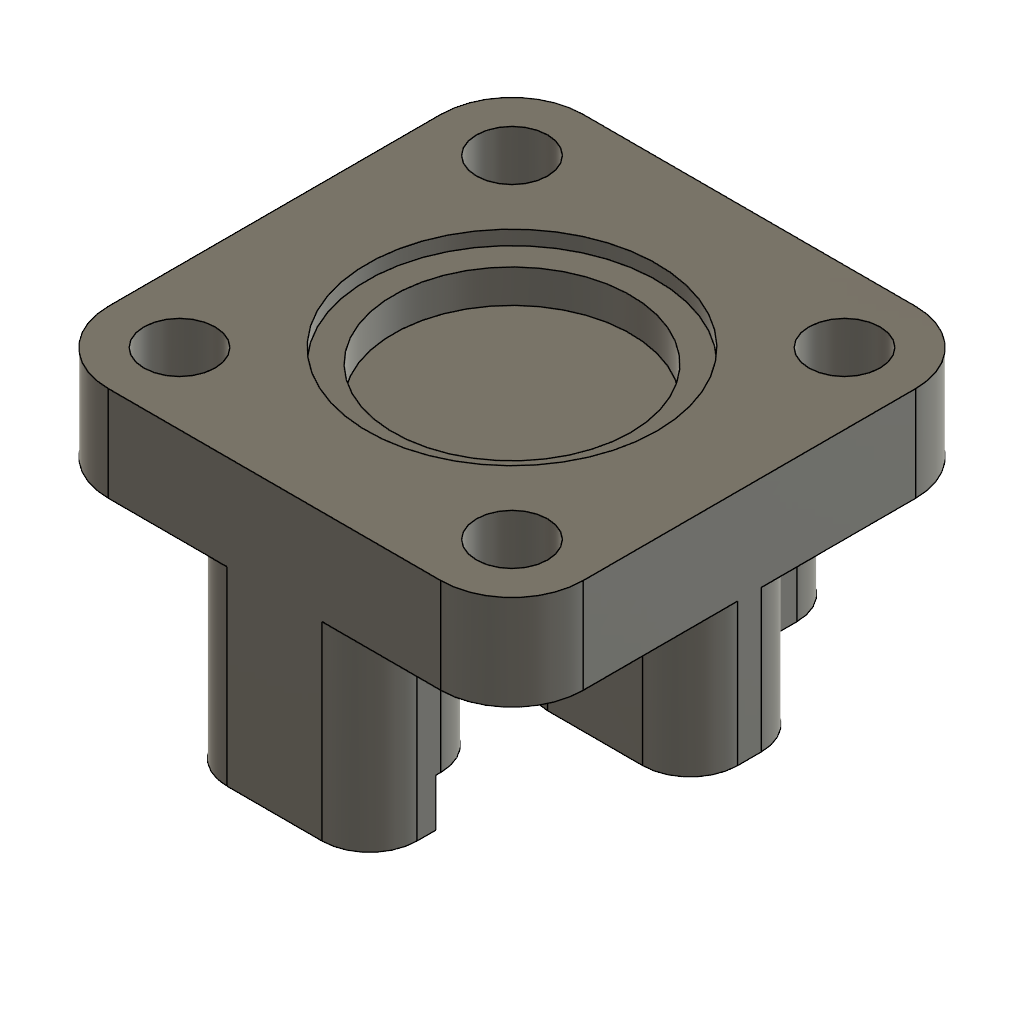
02-20_베어링커버 (Autodesk Fusion 360 design; units mm, degrees)
Autodesk Fusion 360 part; units mm, degrees
sketch "스케치1" plane through (0, 0, 0) normal (0, 1, 0) x (1, 0, 0)
  line L0 (-7, 10) -> (7, 10)
  line L1 (10, 7) -> (10, -7)
  line L2 (7, -10) -> (-7, -10)
  line L3 (-10, -7) -> (-10, 7)
  line L4 (0, 10) -> (0, -10) construction
  arc A0 (-7, 10) -> (-10, 7) centre (-7, 7) ccw
  arc A1 (10, 7) -> (7, 10) centre (7, 7) ccw
  arc A2 (7, -10) -> (10, -7) centre (7, -7) ccw
  arc A3 (-10, -7) -> (-7, -10) centre (-7, -7) ccw
  point P0 (-10, 10)
  point P1 (10, 10)
  point P2 (10, -10)
  dimension "d1" = 20
  dimension "d2" = 20
  dimension "d3" = 3
  constraint horizontal L0
  constraint vertical L1
  constraint horizontal L2
  constraint vertical L3
  constraint midpoint origin L4
  constraint coincident L0 L4.start
  constraint coincident P0 L3
  constraint coincident P0 L0
  constraint tangent L3 A0
  constraint tangent L0 A0
  constraint coincident P1 L0
  constraint coincident P1 L1
  constraint tangent L0 A1
  constraint tangent L1 A1
  constraint equal A0 A1
  constraint coincident L2 L4.end
  constraint coincident P2 L1
  constraint coincident P2 L2
  constraint tangent L1 A2
  constraint tangent L2 A2
  constraint equal A0 A2
  constraint tangent L2 A3
  constraint tangent L3 A3
  constraint equal A0 A3
  measures "d1" distance of P0 P1
  measures "d2" distance of P1 P2
  measures "d3" radius of A0
extrude "돌출1" add sketch "스케치1" along normal blind 4
sketch "스케치2" plane through (0, 4, 0) normal (0, 1, 0) x (-1, 0, 0)
  arc A0 (7, -10) -> (10, -7) centre (7, -7) ccw
  line L0 (10, -7) -> (10, 7)
  arc A1 (10, 7) -> (7, 10) centre (7, 7) ccw
  line L1 (7, 10) -> (-7, 10)
  arc A2 (-7, 10) -> (-10, 7) centre (-7, 7) ccw
  line L2 (-10, 7) -> (-10, -7)
  arc A3 (-10, -7) -> (-7, -10) centre (-7, -7) ccw
  line L3 (-7, -10) -> (7, -10)
  circle A4 centre (0, 0) radius 6.1
  circle A5 centre (0, 0) radius 5
  circle A6 centre (7, -7) radius 1.5
  circle A7 centre (-7, -7) radius 1.5
  circle A8 centre (-7, 7) radius 1.5
  circle A9 centre (7, 7) radius 1.5
  dimension "d6" = 12.2
  dimension "d7" = 10
  dimension "d12" = 3
  dimension "d13" = 3
  dimension "d14" = 3
  dimension "d15" = 3
  constraint coincident A4.centre A5.centre
  constraint concentric A4 A5
  constraint concentric A0 A6
  constraint concentric A3 A7
  constraint concentric A2 A8
  constraint concentric A1 A9
  measures "d6" diameter of A4
  measures "d7" diameter of A5
  measures "d12" diameter of A6
  measures "d13" diameter of A7
  measures "d14" diameter of A8
  measures "d15" diameter of A9
extrude "돌출2" cut sketch "스케치2" against normal blind 2 contours A5
extrude "돌출3" cut sketch "스케치2" against normal blind 0.6 contours A4
extrude "돌출4" cut sketch "스케치2" against normal blind 4 contours A6 | A7 | A8 | A9
sketch "스케치3" plane through (0, 0, 0) normal (0, -1, 0) x (1, 0, 0)
  circle A0 centre (7, 7) radius 1.5
  circle A1 centre (7, -7) radius 1.5
  circle A2 centre (-7, 7) radius 1.5
  circle A3 centre (-7, -7) radius 1.5
  arc A4 (-10, -7) -> (-7, -10) centre (-7, -7) ccw
  line L0 (-7, -10) -> (7, -10)
  arc A5 (7, -10) -> (10, -7) centre (7, -7) ccw
  line L1 (10, -7) -> (10, 7)
  arc A6 (10, 7) -> (7, 10) centre (7, 7) ccw
  line L2 (7, 10) -> (-7, 10)
  arc A7 (-7, 10) -> (-10, 7) centre (-7, 7) ccw
  line L3 (-10, 7) -> (-10, -7)
  line L4 (-2, 10) -> (2, 10)
  line L5 (4, 8) -> (4, 7)
  line L6 (2, 5) -> (-2, 5)
  line L7 (-4, 7) -> (-4, 8)
  line L8 (0, 10) -> (0, -10) construction
  line L9 (-10, 0) -> (10, 0) construction
  arc A8 (-2, 10) -> (-4, 8) centre (-2, 8) ccw
  arc A9 (-4, 7) -> (-2, 5) centre (-2, 7) ccw
  arc A10 (2, 5) -> (4, 7) centre (2, 7) ccw
  arc A11 (4, 8) -> (2, 10) centre (2, 8) ccw
  line L10 (4, -8) -> (4, -7)
  arc A12 (2, -10) -> (4, -8) centre (2, -8) ccw
  line L11 (-2, -10) -> (2, -10)
  arc A13 (-4, -8) -> (-2, -10) centre (-2, -8) ccw
  line L12 (-4, -7) -> (-4, -8)
  arc A14 (-2, -5) -> (-4, -7) centre (-2, -7) ccw
  line L13 (2, -5) -> (-2, -5)
  arc A15 (4, -7) -> (2, -5) centre (2, -7) ccw
  line L14 (-4, 7.2) -> (4, 7.2)
  line L15 (-4, -7.2) -> (4, -7.2)
  line L16 (4, 2.5) -> (8, 2.5)
  line L17 (10, 0.5) -> (10, -0.5)
  line L18 (8, -2.5) -> (4, -2.5)
  line L19 (2, -0.5) -> (2, 0.5)
  circle A16 centre (6, 0) radius 1.1
  arc A17 (4, 2.5) -> (2, 0.5) centre (4, 0.5) ccw
  arc A18 (10, 0.5) -> (8, 2.5) centre (8, 0.5) ccw
  arc A19 (8, -2.5) -> (10, -0.5) centre (8, -0.5) ccw
  arc A20 (2, -0.5) -> (4, -2.5) centre (4, -0.5) ccw
  point P0 (-4, 10)
  point P1 (4, 10)
  point P2 (-4, 5)
  point P3 (2, 2.5)
  point P4 (10, 2.5)
  point P5 (10, -2.5)
  dimension "d18" = 8
  dimension "d19" = 5
  dimension "d20" = 2
  dimension "d21" = 2.8
  dimension "d22" = 5
  dimension "d23" = 8
  dimension "d24" = 2.2
  dimension "d25" = 4
  dimension "d26" = 2
  constraint horizontal L4
  constraint vertical L5
  constraint horizontal L6
  constraint vertical L7
  constraint coincident L2 P0
  constraint midpoint L2 L8.start
  constraint midpoint L0 L8.end
  constraint midpoint L3 L9.start
  constraint midpoint L1 L9.end
  constraint coincident L4 L8.start
  constraint coincident P0 L7
  constraint tangent L7 A8
  constraint tangent L4 A8
  constraint coincident P2 L6
  constraint coincident P2 L7
  constraint tangent L6 A9
  constraint tangent L7 A9
  constraint equal A8 A9
  constraint tangent L5 A10
  constraint tangent L6 A10
  constraint equal A8 A10
  constraint coincident P1 L4
  constraint coincident P1 L5
  constraint tangent L4 A11
  constraint tangent L5 A11
  constraint equal A8 A11
  constraint symmetric L9 L7.end A13.start
  constraint symmetric L9 L4.start L11.start
  constraint symmetric L9 A8 A13
  constraint symmetric L9 L6.end A14.start
  constraint symmetric L9 L7.start L12.start
  constraint symmetric L9 A9 A14
  constraint symmetric L9 L5.end L10.end
  constraint symmetric L9 L6.start L13.start
  constraint symmetric L9 A10 A15
  constraint symmetric L9 L4.end A12.start
  constraint symmetric L9 L5.start L10.start
  constraint symmetric L9 A11 A12
  constraint coincident L7 L14.start
  constraint coincident L5 L14.end
  constraint parallel L4 L14
  constraint symmetric L9 L14.start L15.start
  constraint symmetric L9 L14.end L15.end
  constraint horizontal L16
  constraint vertical L17
  constraint horizontal L18
  constraint vertical L19
  constraint coincident L1 P5
  constraint coincident L9 A16.centre
  constraint coincident P3 L16
  constraint coincident P3 L19
  constraint tangent L16 A17
  constraint tangent L19 A17
  constraint coincident L9.end L17
  constraint coincident P4 L16
  constraint coincident P4 L17
  constraint tangent L16 A18
  constraint tangent L17 A18
  constraint equal A17 A18
  constraint coincident P5 L18
  constraint tangent L17 A19
  constraint tangent L18 A19
  constraint equal A17 A19
  constraint tangent L18 A20
  constraint tangent L19 A20
  constraint equal A17 A20
  measures "d18" distance of P0 P1
  measures "d19" distance of P0 P2
  measures "d20" radius of A8
  measures "d21" distance of L4 L14
  measures "d22" distance of P4 P5
  measures "d23" distance of P3 P4
  measures "d24" diameter of A16
  measures "d25" distance of L17 A16.centre
  measures "d26" radius of A17
extrude "돌출5" add sketch "스케치3" along normal blind 8 contours L0 L10 A12 L11 A13 L12 L15 | L2 L4 L5 L7 A8 A11 L14
extrude "돌출6" add sketch "스케치3" along normal blind 6 contours L10 L12 A14 L13 A15 L15 | L5 L6 L7 A9 A10 L14 | L1 L16 L17 L18 L19 A17 A18 A19 A20
